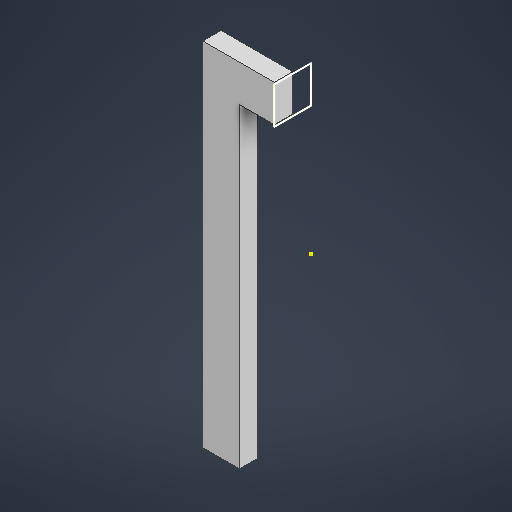
# Autodesk Inventor part: Pieza2
Saved by Autodesk Inventor 2025.2 (Build 292293000, 293)
## iProperties
Created: 2025-06-10
Part Number: Pieza2
Material: Genérico
Document SubType Name: Modeling
Designer: Niko
Density: 1 g/cm^3
Appearance: Valor por defecto
Author: Niko
Autodesk Inventor part; units mm, degrees
ref_plane "YZ Plane" through (0, 0, 0) normal (1, 0, 0) x (0, 1, 0)
ref_plane "XZ Plane" through (0, 0, 0) normal (0, 1, 0) x (-1, 0, 0)
ref_plane "XY Plane" through (0, 0, 0) normal (0, 0, 1) x (1, 0, 0)
sketch "Boceto1" plane through (0, 0, 0) normal (0, 0, 1) x (1, 0, 0)
  line L0 (0, 0) -> (0, 45)
  line L1 (0, 0) -> (0, -45)
  line L2 (0, 45) -> (10, 45)
  line L3 (10, 45) -> (10, -45)
  line L4 (10, -45) -> (0, -45)
  dimension "d0" = 45
  dimension "d1" = 45
  dimension "d2" = 10
  dimension "d3" = 90
  constraints: 10 end point, 2 vertical, 1 horizontal, 1 perpendicular
  measures "d0" distance of L0.start L0.end
  measures "d1" distance of L0.start L1.end
  measures "d2" distance of L0.end L2.end
  measures "d3" distance of L2.end L3.end
extrude "Extrusión1" add sketch "Boceto1" along normal blind 10
sketch "Boceto2" plane through (10, -45, 0) normal (1, 0, 0) x (0, 0, -1)
  line L0 (-10, 0) -> (-10, 90) projected
  line L1 (-10, 90) -> (0, 90)
  line L2 (0, 90) -> (0, 80)
  line L3 (0, 80) -> (-10, 80)
  line L4 (-10, 80) -> (-10, 90)
  point P0 (0, 45)
  dimension "d6" = 10
  dimension "d7" = 10
  constraints: 8 end point, 2 parallel, 1 horizontal, 1 perpendicular
  measures "d6" distance of L2.end L3.end
  measures "d7" distance of L1.end L2.end
extrude "Extrusión2" add sketch "Boceto2" along normal blind 10
sketch "Boceto3" plane through (0, -45, 0) normal (0, -1, 0) x (1, 0, 0)
  line L0 (10, 0) -> (10, 10) projected
  line L1 (0, 10) -> (10, 10)
  line L2 (10, 10) -> (10, 0)
  line L3 (10, 0) -> (0, 0)
  line L4 (0, 0) -> (0, 10)
  constraints: 8 end point, 2 parallel, 1 horizontal, 1 perpendicular
extrude "Extrusión3" cut sketch "Boceto3" against normal blind 0.5
sketch "Boceto4" plane through (20, -45, 0) normal (1, 0, 0) x (0, 0, -1)
  line L0 (0, 80) -> (-10, 80) projected
  line L1 (-10, 90) -> (-10, 80) projected
  line L2 (0, 80) -> (-10, 80)
  line L3 (-10, 80) -> (-10, 90)
  line L4 (-10, 90) -> (0, 90)
  line L5 (0, 90) -> (0, 80)
  point P0 (0, 45)
  constraints: 8 end point, 2 parallel, 1 horizontal, 1 perpendicular
sketch "Boceto5" plane through (0, -44.5, 0) normal (0, -1, 0) x (1, 0, 0)
  line L0 (0, 0) -> (20, 0) projected
  line L1 (0, 10) -> (20, 10) projected
  line L2 (10, 0) -> (0, 0)
  line L3 (0, 0) -> (0, 10)
  line L4 (0, 10) -> (10, 10)
  line L5 (10, 10) -> (10, 0)
  constraints: 8 end point, 2 parallel, 1 horizontal, 1 midpoint, 1 perpendicular
extrude "Extrusión4" cut sketch "Boceto5" against normal blind 0.5
sketch "Boceto6" plane through (20, -45, 0) normal (1, 0, 0) x (0, 0, -1)
  line L0 (0, 90) -> (-10, 90) projected
  line L1 (0, 80) -> (-10, 80)
  line L2 (-10, 80) -> (-10, 90)
  line L3 (-10, 90) -> (0, 90)
  line L4 (0, 90) -> (0, 80)
  point P0 (0, 45)
  constraints: 8 end point, 2 parallel, 1 horizontal, 1 perpendicular
extrude "Extrusión5" cut sketch "Boceto6" against normal blind 0.5
sketch "Boceto7" plane through (0, 0, 10) normal (0, 0, 1) x (1, 0, 0)
  line L0 (-10.4131, 45.8882) -> (20.2967, 45.8882)
  line L1 (20.2967, 45.8882) -> (20.2967, -44.6528)
  line L2 (20.2967, -44.6528) -> (-10.4131, -44.6528)
  line L3 (-10.4131, -44.6528) -> (-10.4131, 45.8882)
  point P0 (0, 0)
  constraints: 8 end point, 2 parallel, 1 horizontal, 1 perpendicular
extrude "Extrusión6" cut sketch "Boceto7" against normal blind 0.5
sketch "Boceto8" plane through (0, 0, 0) normal (0, 0, -1) x (-1, 0, 0)
  line L0 (10.6685, 49.7383) -> (-26.8155, 49.7383)
  line L1 (-26.8155, 49.7383) -> (-26.8155, -49.7383)
  line L2 (-26.8155, -49.7383) -> (10.6685, -49.7383)
  line L3 (10.6685, -49.7383) -> (10.6685, 49.7383)
  point P0 (0, 0)
  constraints: 8 end point, 2 parallel, 1 horizontal, 1 perpendicular
extrude "Extrusión7" cut sketch "Boceto8" against normal blind 4.5
sketch "Boceto9" plane through (0, -44, 0) normal (0, -1, 0) x (1, 0, 0)
  line L0 (10, 9.5) -> (0, 9.5) projected
  line L1 (0, 4.5) -> (10, 4.5) projected
  line L2 (10, 9.5) -> (0, 9.5)
  line L3 (0, 9.5) -> (0, 4.5)
  line L4 (0, 4.5) -> (10, 4.5)
  line L5 (10, 4.5) -> (10, 9.5)
  point P0 (0, 0)
  constraints: 8 end point, 2 parallel, 1 horizontal, 1 perpendicular
extrude "Extrusión8" add sketch "Boceto9" along normal blind 6.1
sketch "Boceto10" plane through (0, -50.1, 0) normal (0, -1, 0) x (1, 0, 0)
  line L0 (0, 4.5) -> (0, 9.5) projected
  line L1 (10, 4.5) -> (10, 9.5) projected
  line L2 (0, 9.5) -> (10, 9.5)
  line L3 (10, 9.5) -> (10, 4.5)
  line L4 (10, 4.5) -> (0, 4.5)
  line L5 (0, 4.5) -> (0, 9.5)
  point P0 (0, 0)
  constraints: 8 end point, 2 parallel, 1 horizontal, 1 perpendicular
extrude "Extrusión9" add sketch "Boceto10" along normal blind 0.9
